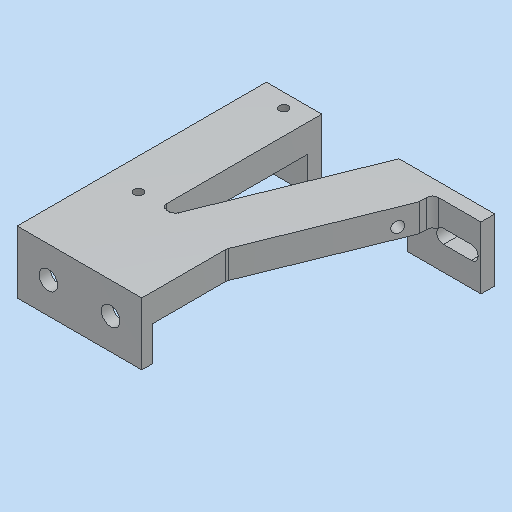
# Autodesk Inventor part: SE0004AN000_G01_353
Saved by Autodesk Inventor 2023.3 (Build 273359000, 359)
## iProperties
RuleStatus: InUse
Created: 2021-10-07
Part Number: SE0004AN000_G01_353
Material: 3.3547 AlMg4,5Mn0,7 - AW 5083
Description: =<RBPARTNOTITLE2>
Document SubType Name: Modeling
Designer: brt9bw
Mass: 836.149 g
Surface Area: 633.577 cm^2
Volume: 314.342 cm^3
Density: 2.66 g/cm^3
Appearance: Aluminium AnP
AnP_Kategorie: 1
AnP_Material: =<Material>
MaxAbmaße: 45 x 180 x 165 (FM)
AnP_TemplVers: 20200821
RBDOCUMENTTYPE: DRF
RBDOCUMENTVERSION: 00
RBDRAWINGMAINSCALE: 1:1
RBDRAWINGMISSINGSPEC: --
RBDRAWINGVOLUME: --
RBDSV1: 0850
RBGBEDGESIN1: +0,5
RBGBEDGESIN2: +0,2
RBGBEDGESOUT1: -0,3
RBGBEDGESOUT2: -0,1
RBMATERIAL: =<Material>
RBMATMEETS: --
RBMATNO: =<Part Number>
RBPARTMADEOF: 45 x 180 x 165 (FM)
RBPARTNO: SIEHE MNR
RBPARTNOTITLE1: manufactured part
RBPARTNOTITLE2: Anfertigungsteil
RBPARTSAFETYINDICATOR: --
RBSURFACE: anodised colourless
RBSURFACE2: eloxiert farblos
RBZEDGESNORM: ISO13715:2002-06
RBZGENDIMCLASS: m
RBZGENDIMNORM: ISO 2768-1:1989-11
RBZGENGEOCLASS: H
RBZGENGEONORM: ISO 2768-2:1989-11
RBZSURFACENORM: ISO13D2:2002-02
RBZTOLERANCENORM: ISO 14405-1:2010-12
Author: brt9bw
Keywords: =<RBPARTMADEOF>
Comments: =<RBSURFACE2>
Revision Number: 01
Autodesk Inventor part; units mm, degrees
ref_plane "YZ Plane" through (0, 0, 0) normal (1, 0, 0) x (0, 1, 0)
ref_plane "XZ Plane" through (0, 0, 0) normal (0, 1, 0) x (-1, 0, 0)
ref_plane "XY Plane" through (0, 0, 0) normal (0, 0, 1) x (1, 0, 0)
sketch "Skizze1" plane through (0, 0, 0) normal (0, 0, 1) x (1, 0, 0)
  line L0 (0, 0) -> (165, 0)
  line L1 (165, 0) -> (165, 180)
  line L2 (165, 180) -> (0, 180)
  line L3 (0, 180) -> (0, 0)
  dimension "d0" = 165
  dimension "d1" = 180
  constraints: 8 end point, 2 parallel, 1 horizontal, 1 perpendicular
  measures "d0" distance of L2.end L1.end
  measures "d1" distance of L1.end L0.end
extrude "Extrusion1" add sketch "Skizze1" against normal blind 45
sketch "Skizze2" plane through (0, 0, 0) normal (0, 0, 1) x (1, 0, 0)
  line L0 (165, 0) -> (165, 180) projected
  line L1 (165, 180) -> (0, 180) projected
  line L2 (0, 180) -> (0, 0) projected
  line L3 (0, 0) -> (165, 0) projected
  line L4 (40, 175) -> (40, 64)
  line L5 (40, 64) -> (49, 64)
  line L6 (49, 64) -> (93.8469, 175)
  line L7 (93.8469, 175) -> (40, 175)
  dimension "d4" = 40
  dimension "d5" = 5
  dimension "d6" = 116
  dimension "d7" = 112
  dimension "d8" = 49
  constraints: 8 end point, 1 parallel, 1 perpendicular, 1 vertical
  measures "d4" distance between parallel lines of L2 L4
  measures "d5" distance between parallel lines of L1 L7
  measures "d6" distance between parallel lines of L1 L5
  measures "d7" angle of L5 L6
  measures "d8" distance from line of L5.end L2
extrude "Extrusion2" cut sketch "Skizze2" against normal through all contours L7 L6 L5 L4
sketch "Skizze3" plane through (0, 0, 0) normal (0, 0, 1) x (1, 0, 0)
  line L0 (93.8469, 175) -> (49, 64) projected
  line L1 (49, 64) -> (40, 64) projected
  line L2 (40, 64) -> (40, 175) projected
  line L3 (40, 175) -> (93.8469, 175) projected
  line L4 (165, 0) -> (165, 180) projected
  line L5 (165, 180) -> (0, 180) projected
  line L6 (0, 180) -> (0, 0) projected
  line L7 (0, 0) -> (165, 0) projected
  line L8 (90, 61.3693) -> (130, 160.3728)
  line L9 (130, 160.3728) -> (130, 170)
  line L10 (130, 170) -> (165, 170)
  line L11 (90, 61.3693) -> (90, 0)
  dimension "d11" = 35
  dimension "d12" = 39
  dimension "d13" = 10
  dimension "d14" = 90
  constraints: 8 end point, 3 perpendicular, 2 point on line, 1 parallel
  measures "d11" distance of L9.end L10.end
  measures "d12" distance between parallel lines of L0 L8
  measures "d13" distance between parallel lines of L5 L10
  measures "d14" distance between parallel lines of L6 L11
extrude "Extrusion3" cut sketch "Skizze3" against normal through all contours L7 L11 L8 L9 L10 L4
sketch "Skizze4" plane through (0, 0, -45) normal (0, 0, -1) x (-1, 0, 0)
  line L0 (-90, 61.3693) -> (-90, 0) projected
  line L1 (-90, 0) -> (0, 0) projected
  line L2 (0, 0) -> (0, 180) projected
  line L3 (0, 180) -> (-165, 180) projected
  line L4 (-165, 180) -> (-165, 170) projected
  line L5 (-165, 170) -> (-130, 170) projected
  line L6 (-130, 170) -> (-130, 160.3728) projected
  line L7 (-130, 160.3728) -> (-90, 61.3693) projected
  line L8 (-49, 64) -> (-93.8469, 175) projected
  line L9 (-93.8469, 175) -> (-40, 175) projected
  line L10 (-40, 175) -> (-40, 64) projected
  line L11 (-40, 64) -> (-49, 64) projected
  line L12 (0, 170) -> (-165, 170)
  line L13 (-165, 170) -> (-165, 8)
  line L14 (-165, 8) -> (0, 8)
  line L15 (0, 8) -> (0, 170)
  line L16 (-165, 180) -> (-165, 170) projected
  point P0 (0, 8)
  dimension "d17" = 8
  dimension "d18" = 10
  constraints: 8 end point, 2 parallel, 1 collinear, 1 horizontal, 1 perpendicular, 1 point on line
  measures "d17" distance between parallel lines of L14 L1
  measures "d18" distance between parallel lines of L3 L12
extrude "Extrusion4" cut sketch "Skizze4" against normal blind 25 contours L7 L6 L12 L8 L11 L10 L2 L14 L0 | L0 L14 L13 L5 L6 L7 | L12 L10 L11 L8
sketch "Skizze5" plane through (93.8469, 175, -45) normal (-0.9271839, 0.3746066, 0) x (0, 0, 1)
  line L0 (25, -5.3927) -> (25, -119.7174) projected
  line L1 (45, -119.7174) -> (25, -119.7174) projected
  line L2 (45, 0) -> (45, -119.7174) projected
  line L3 (45, 0) -> (0, 0) projected
  line L4 (0, -5.3927) -> (0, 0) projected
  line L5 (0, -5.3927) -> (25, -5.3927) projected
  line L6 (45, 31.2903) -> (45, -30.5198) projected
  line L7 (45, 31.2903) -> (45, -30.5198) projected
  line L8 (45, 31.2903) -> (0, 31.2903) projected
  line L9 (0, -30.5198) -> (0, 31.2903) projected
  line L10 (45, -30.5198) -> (0, -30.5198) projected
  line L11 (45, 31.2903) -> (0, 31.2903) projected
  point P0 (45, -197.4128)
  point P1 (32.5, -11.8927)
  dimension "d21" = 7.5
  dimension "d81" = 6.5
  measures "d21" distance from line of point (32.5, -11.893) L0
  measures "d81" distance from line of point (32.5, -11.893) L5
hole "Bohrung1" at (89.3918, 163.9733, -12.5) direction (0.9271839, -0.3746066, 0) diameter 8 end through all
sketch "Skizze6" plane through (0, 180, 0) normal (0, 1, 0) x (1, 0, 0)
  line L0 (165, 0) -> (0, 0) projected
  line L1 (165, 0) -> (165, 45) projected
  line L2 (0, 45) -> (165, 45) projected
  line L3 (0, 0) -> (0, 45) projected
  point P0 (22.5, 22.5)
  dimension "d31" = 22.5
  dimension "d32" = 22.5
  measures "d31" distance from line of point (22.5, 22.5) L3
  measures "d32" distance from line of point (22.5, 22.5) L0
hole "Bohrung2" at (22.5, 180, -22.5) direction (0, -1, 0) diameter 10.106 depth 28 tip angle 118 thread size "M12x1.75" designation "M12" class "6H" standard "ISO Metric profile"
sketch "Skizze7" plane through (0, 0, -45) normal (0, -1, 0) x (1, 0, 0)
  line L0 (90, 0) -> (90, 45) projected
  line L1 (0, 45) -> (90, 45) projected
  line L2 (0, 45) -> (0, 0) projected
  line L3 (90, 0) -> (0, 0) projected
  point P0 (22.5, 22.5)
  point P1 (67.5, 22.5)
  dimension "d40" = 45
  dimension "d41" = 22.5
  dimension "d42" = 22.5
  constraints: 1 horizontal alignment
  measures "d40" distance of point (67.5, 22.5) point (22.5, 22.5)
  measures "d41" distance from line of point (22.5, 22.5) L2
  measures "d42" distance from line of L3 point (22.5, 22.5)
hole "Bohrung3" at (22.5, 0, -22.5) at (67.5, 0, -22.5) direction (0, 1, 0) diameter 13.5 depth 28 tip angle 118 clearance for "Inbusschraube ISO 4762  versenkt" size "M12" standard "ISO"
sketch "Skizze8" plane through (0, 0, -20) normal (0, 0, -1) x (-1, 0, 0)
  line L0 (-16.23, 28) -> (-16.23, 8) projected
  line L1 (0, 8) -> (-16.23, 8) projected
  line L2 (0, 170) -> (0, 8) projected
  line L3 (-18.1088, 170) -> (0, 170) projected
  line L4 (-18.1088, 170) -> (-18.1088, 152) projected
  line L5 (-26.8912, 152) -> (-26.8912, 170) projected
  line L6 (-40, 170) -> (-26.8912, 170) projected
  line L7 (-40, 64) -> (-40, 170) projected
  line L8 (-49, 64) -> (-40, 64) projected
  line L9 (-91.8268, 170) -> (-49, 64) projected
  line L10 (-130, 170) -> (-91.8268, 170) projected
  line L11 (-90, 61.3693) -> (-130, 160.3728) projected
  line L12 (-90, 8) -> (-90, 61.3693) projected
  line L13 (-73.77, 8) -> (-90, 8) projected
  line L14 (-73.77, 8) -> (-73.77, 28) projected
  line L15 (-61.23, 28) -> (-61.23, 8) projected
  line L16 (-28.77, 8) -> (-61.23, 8) projected
  line L17 (-28.77, 8) -> (-28.77, 28) projected
  line L18 (-82, 8) -> (-8, 8)
  line L19 (-8, 8) -> (-8, 48)
  line L20 (-8, 48) -> (-82, 48)
  line L21 (-82, 48) -> (-82, 8)
  line L22 (-130, 160.3728) -> (-130, 170) projected
  point P0 (0, 0)
  point P1 (-8, 8)
  dimension "d50" = 8
  dimension "d51" = 8
  dimension "d52" = 40
  constraints: 8 end point, 3 horizontal alignment, 2 parallel, 1 horizontal, 1 perpendicular, 1 point on line
  measures "d50" distance between parallel lines of L21 L12
  measures "d51" distance between parallel lines of L2 L19
  measures "d52" distance between parallel lines of L20 L18
extrude "Extrusion5" cut sketch "Skizze8" against normal blind 10
sketch "Skizze9" plane through (0, 180, 0) normal (0, 1, 0) x (1, 0, 0)
  line L0 (165, 0) -> (0, 0) projected
  line L1 (165, 0) -> (165, 45) projected
  point P0 (148, 22.5)
  dimension "d55" = 22.5
  dimension "d56" = 17
  measures "d55" distance from line of L0 point (148, 22.5)
  measures "d56" distance from line of L1 point (148, 22.5)
hole "Bohrung4" at (148, 180, -22.5) direction (0, -1, 0) diameter 6.6 depth 28 tip angle 118 clearance for "Inbusschraube ISO 4762  versenkt" size "M6" standard "ISO"
fillet "Rundung1" radius 4 4 edges at (40, 175, -22.5) (40, 64, -10) (49, 64, -10) (130, 170, -10)
fillet "Rundung2" radius 4 4 edges at (8, 8, -15) (8, 48, -15) (82, 48, -15) (82, 8, -15)
fillet "Rundung3" radius 3 1 edges at (93.8469, 175, -22.5)
sketch "Skizze10" plane through (0, 0, 0) normal (0, 0, 1) x (1, 0, 0)
  line L0 (134, 170) -> (165, 170) projected
  line L1 (165, 170) -> (165, 180) projected
  line L2 (165, 180) -> (0, 180) projected
  line L3 (0, 180) -> (0, 0) projected
  line L4 (0, 0) -> (90, 0) projected
  line L5 (90, 0) -> (90, 61.3693) projected
  line L6 (90, 61.3693) -> (130, 160.3728) projected
  line L7 (92.1808, 170.8762) -> (50.0107, 66.5016) projected
  arc A0 (46.302, 64) -> (50.0107, 66.5016) centre (46.302, 68) ccw projected
  line L8 (46.302, 64) -> (44, 64) projected
  arc A1 (40, 68) -> (44, 64) centre (44, 68) ccw projected
  line L9 (40, 68) -> (40, 171) projected
  arc A2 (44, 175) -> (40, 171) centre (44, 171) ccw projected
  line L10 (44, 175) -> (89.3992, 175) projected
  arc A3 (92.1808, 170.8762) -> (89.3992, 175) centre (89.3992, 172) ccw projected
  line L11 (40, 171) -> (40, 180)
  line L12 (92.1808, 170.8762) -> (95.867, 180)
  line L13 (95.867, 180) -> (40, 180)
  line L14 (130, 160.3728) -> (130, 166) projected
  arc A4 (134, 170) -> (130, 166) centre (134, 166) ccw projected
  point P0 (40.3765, 172.6941)
  constraints: 6 end point, 2 point on line, 1 collinear, 1 perpendicular, 1 tangent, 1 vertical
extrude "Extrusion6" cut sketch "Skizze10" against normal through all contours L12 A3 L10 A2 L11 L2
sketch "Skizze11" plane through (91.8268, 170, -45) normal (0, -1, 0) x (1, 0, 0)
  line L0 (42.1732, 25) -> (42.1732, 45) projected
  line L1 (42.1732, 25) -> (0, 25) projected
  line L2 (0, 0) -> (0, 25) projected
  line L3 (73.1732, 0) -> (0, 0) projected
  line L4 (73.1732, 45) -> (73.1732, 0) projected
  line L5 (42.1732, 45) -> (73.1732, 45) projected
  circle A0 centre (56.1732, 22.5) radius 3.3 projected
  line L6 (46.1732, 22.5) -> (66.1732, 22.5) construction
  line L7 (46.1732, 17.5) -> (66.1732, 17.5)
  line L8 (66.1732, 27.5) -> (46.1732, 27.5)
  arc A1 (46.1732, 27.5) -> (46.1732, 17.5) centre (46.1732, 22.5) ccw
  arc A2 (66.1732, 17.5) -> (66.1732, 27.5) centre (66.1732, 22.5) ccw
  point P0 (-91.8268, 45)
  dimension "d69" = 10
  dimension "d70" = 20
  constraints: 8 end point, 4 point on circle, 4 tangent, 2 centre point, 1 midpoint, 1 parallel, 1 perpendicular
  measures "d69" diameter of A2
  measures "d70" distance of L6.end L6.start
extrude "Extrusion7" cut sketch "Skizze11" against normal through all contours L1 A1 L0 | L0 A1 L8 A2 L7 L1 | A0
sketch "Skizze12" plane through (165, 180, 0) normal (0, 1, 0) x (1, 0, 0)
  line L0 (-7, 17.5) -> (-27, 17.5) projected
  arc A0 (-27, 27.5) -> (-27, 17.5) centre (-27, 22.5) ccw projected
  line L1 (-27, 27.5) -> (-7, 27.5) projected
  arc A1 (-7, 17.5) -> (-7, 27.5) centre (-7, 22.5) ccw projected
  line L2 (0, 0) -> (-69.133, 0) projected
  line L3 (0, 0) -> (0, 45) projected
  line L4 (-165, 45) -> (-125, 45) projected
  line L5 (-125, 0) -> (-125, 45) projected
  line L6 (-165, 0) -> (-165, 45) projected
  line L7 (-125, 0) -> (-165, 0) projected
  line L8 (-69.133, 45) -> (-69.133, 0) projected
  line L9 (-69.133, 45) -> (0, 45) projected
  point P0 (-56, 22.5)
  dimension "d73" = 56
  constraints: 1 horizontal alignment
  measures "d73" distance from line of point (-56, 22.5) L3
hole "Bohrung5" at (109, 180, -22.5) direction (0, -1, 0) diameter 10 depth 10 tip angle 118
fillet "Rundung4" radius 4 1 edges at (90, 61.3693, -10)
sketch "Skizze13" plane through (91.8268, 170, -45) normal (0, -1, 0) x (1, 0, 0)
  arc A0 (12.8431, 25) -> (21.5033, 25) centre (17.1732, 22.5) ccw projected
  line L0 (12.8431, 25) -> (0, 25) projected
  line L1 (0, 0) -> (0, 25) projected
  line L2 (73.1732, 0) -> (0, 0) projected
  line L3 (73.1732, 45) -> (73.1732, 0) projected
  line L4 (42.1732, 45) -> (73.1732, 45) projected
  line L5 (42.1732, 25.5) -> (42.1732, 45) projected
  arc A1 (46.1732, 27.5) -> (42.1732, 25.5) centre (46.1732, 22.5) ccw projected
  line L6 (46.1732, 27.5) -> (66.1732, 27.5) projected
  arc A2 (66.1732, 17.5) -> (66.1732, 27.5) centre (66.1732, 22.5) ccw projected
  line L7 (66.1732, 17.5) -> (46.1732, 17.5) projected
  arc A3 (41.8431, 25) -> (46.1732, 17.5) centre (46.1732, 22.5) ccw projected
  line L8 (41.8431, 25) -> (21.5033, 25) projected
  line L9 (0, 16.5) -> (20, 16.5)
  line L10 (20, 16.5) -> (20, 0)
  line L11 (20, 0) -> (0, 0)
  line L12 (0, 0) -> (0, 16.5)
  point P0 (-91.8268, 45)
  dimension "d83" = 16.5
  dimension "d84" = 20
  constraints: 8 end point, 2 parallel, 2 point on line, 1 horizontal, 1 perpendicular
  measures "d83" distance between parallel lines of L2 L9
  measures "d84" distance between parallel lines of L10 L12
extrude "Extrusion8" cut sketch "Skizze13" against normal through all contours L9 L10 L2 L1
sketch "Skizze14" plane through (0, 0, 0) normal (0, 0, 1) x (1, 0, 0)
  line L0 (40, 68) -> (40, 180) projected
  line L1 (40, 180) -> (0, 180) projected
  line L2 (0, 180) -> (0, 0) projected
  line L3 (0, 0) -> (90, 0) projected
  line L4 (90, 0) -> (90, 60.5918) projected
  arc A0 (90.2913, 62.0902) -> (90, 60.5918) centre (94, 60.5918) ccw projected
  line L5 (90.2913, 62.0902) -> (130, 160.3728) projected
  line L6 (130, 160.3728) -> (130, 166) projected
  arc A1 (134, 170) -> (130, 166) centre (134, 166) ccw projected
  line L7 (134, 170) -> (165, 170) projected
  line L8 (165, 170) -> (165, 180) projected
  line L9 (165, 180) -> (95.867, 180) projected
  line L10 (95.867, 180) -> (50.0107, 66.5016) projected
  arc A2 (46.302, 64) -> (50.0107, 66.5016) centre (46.302, 68) ccw projected
  line L11 (46.302, 64) -> (44, 64) projected
  arc A3 (40, 68) -> (44, 64) centre (44, 68) ccw projected
  point P0 (22.5, 170)
  point P1 (22.5, 65)
  dimension "d87" = 22.5
  dimension "d89" = 105
  dimension "d97" = 10
  constraints: 1 vertical alignment
  measures "d87" distance from line of point (22.5, 65) L2
  measures "d89" distance of point (22.5, 170) point (22.5, 65)
  measures "d97" distance from line of L1 point (22.5, 170)
hole "Bohrung6" at (22.5, 170, 0) at (22.5, 65, 0) direction (0, 0, -1) diameter 6.647 depth 20 tip angle 118 thread size "M8x1.25" designation "M8" class "6H" standard "ISO Metric profile"
